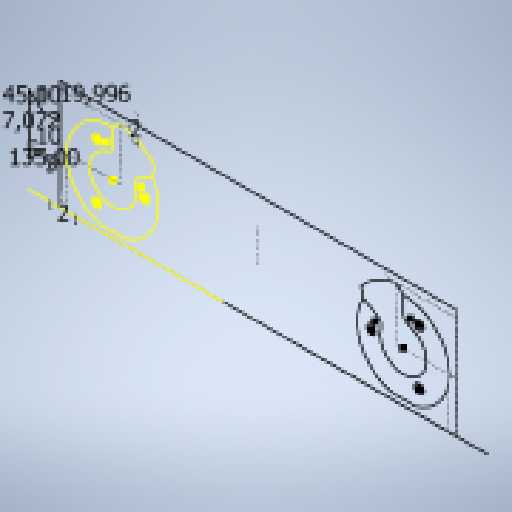
# Autodesk Inventor part: fast_motors
Saved by Autodesk Inventor 2025 (Build 290162000, 162)
## iProperties
Created: 2026-11-07
Part Number: fast_motors
Material: Типовые
Document SubType Name: Modeling
Designer: garin
Density: 1 g/cm^3
Appearance: По умолчанию
Author: garin
Autodesk Inventor part; units mm, degrees
ref_plane "YZ Plane" through (0, 0, 0) normal (1, 0, 0) x (0, 1, 0)
ref_plane "XZ Plane" through (0, 0, 0) normal (0, 1, 0) x (-1, 0, 0)
ref_plane "XY Plane" through (0, 0, 0) normal (0, 0, 1) x (1, 0, 0)
sketch "Эскиз1" plane through (0, 0, 0) normal (0, 0, 1) x (1, 0, 0)
  circle A0 centre (-45.542, 7.686) radius 1.3 projected
  circle A1 centre (-32.0424, -0.108) radius 1.3 projected
  circle A2 centre (-45.542, -7.902) radius 1.3 projected
  arc A3 (-41.0424, 12.892) -> (-44.6131, -12.608) centre (-41.0424, -0.108) ccw projected
  line L0 (-37.4717, -12.608) -> (-44.6131, -12.608) projected
  arc A4 (-37.4717, -12.608) -> (-29.7841, 6.392) centre (-41.0424, -0.108) ccw projected
  line L1 (-33.8879, 4.0227) -> (-29.7841, 6.392) projected
  arc A5 (-33.8879, 4.0227) -> (-34.8066, 1.7262) centre (-32.8879, 2.2906) ccw projected
  arc A6 (-42.5718, 6.2095) -> (-34.8066, 1.7262) centre (-41.0424, -0.108) ccw projected
  arc A7 (-42.5718, 6.2095) -> (-41.0424, 8.1534) centre (-43.0424, 8.1534) ccw projected
  line L2 (-41.0424, 12.892) -> (-41.0424, 8.1534) projected
  arc A8 (-29.1653, 9.0535) -> (-39.0468, 14.7587) centre (-41.0424, -0.108) ccw projected
  line L3 (-29.7841, 6.392) -> (-29.1653, 9.0535) projected
  line L4 (-39.0468, 14.7587) -> (-41.0424, 12.892) projected
  line L5 (-10, -14.25) -> (-65, -14.25) projected
  line L6 (-41.0424, -0.108) -> (-54.0424, -0.108) construction
  line L7 (-54.0424, -0.108) -> (-56.0424, -0.108) construction
  line L8 (-56.0424, -0.108) -> (-56.0424, -14.25) construction
  line L9 (-56.0424, -14.25) -> (-54.0424, -14.25) construction
  line L10 (-54.0424, -14.25) -> (-54.0424, -0.108) construction
  line L11 (-56.0424, -0.108) -> (-39.0468, -0.108) construction
  line L12 (-39.0468, -0.108) -> (-39.0468, 14.7587) construction
  line L13 (-39.0468, 14.7587) -> (-56.0424, 14.7587) construction
  line L14 (-56.0424, 14.7587) -> (-56.0424, -0.108) construction
  line L15 (-56.0424, 14.7587) -> (-36.0464, 14.7587) construction
  line L16 (-36.0464, 14.7587) -> (-36.0464, 16.7587) construction
  line L17 (-36.0464, 16.7587) -> (-56.0424, 16.7587) construction
  line L18 (-56.0424, 16.7587) -> (-56.0424, 14.7587) construction
  line L19 (0, 0) -> (0, 9.0535) construction
  circle A9 centre (45.542, 7.686) radius 1.3
  circle A10 centre (32.0424, -0.108) radius 1.3
  circle A11 centre (45.542, -7.902) radius 1.3
  arc A12 (44.6131, -12.608) -> (41.0424, 12.892) centre (41.0424, -0.108) ccw
  line L20 (37.4717, -12.608) -> (44.6131, -12.608)
  arc A13 (29.7841, 6.392) -> (37.4717, -12.608) centre (41.0424, -0.108) ccw
  line L21 (33.8879, 4.0227) -> (29.7841, 6.392)
  arc A14 (34.8066, 1.7262) -> (33.8879, 4.0227) centre (32.8879, 2.2906) ccw
  arc A15 (34.8066, 1.7262) -> (42.5718, 6.2095) centre (41.0424, -0.108) ccw
  arc A16 (41.0424, 8.1534) -> (42.5718, 6.2095) centre (43.0424, 8.1534) ccw
  line L22 (41.0424, 12.892) -> (41.0424, 8.1534)
  arc A17 (39.0468, 14.7587) -> (29.1653, 9.0535) centre (41.0424, -0.108) ccw
  line L23 (29.7841, 6.392) -> (29.1653, 9.0535)
  line L24 (39.0468, 14.7587) -> (41.0424, 12.892)
  line L25 (10, -14.25) -> (65, -14.25)
  line L26 (41.0424, -0.108) -> (54.0424, -0.108) construction
  line L27 (54.0424, -0.108) -> (56.0424, -0.108) construction
  line L28 (56.0424, -0.108) -> (56.0424, -14.25) construction
  line L29 (56.0424, -14.25) -> (54.0424, -14.25) construction
  line L30 (54.0424, -14.25) -> (54.0424, -0.108) construction
  line L31 (56.0424, -0.108) -> (39.0468, -0.108) construction
  line L32 (39.0468, -0.108) -> (39.0468, 14.7587) construction
  line L33 (39.0468, 14.7587) -> (56.0424, 14.7587) construction
  line L34 (56.0424, 14.7587) -> (56.0424, -0.108) construction
  line L35 (56.0424, 14.7587) -> (36.0464, 14.7587) construction
  line L36 (36.0464, 14.7587) -> (36.0464, 16.7587) construction
  line L37 (36.0464, 16.7587) -> (56.0424, 16.7587) construction
  line L38 (56.0424, 16.7587) -> (56.0424, 14.7587) construction
  line L39 (-56.0424, 16.7587) -> (56.0424, 16.7587)
  line L40 (56.0424, 16.7587) -> (56.0424, -14.25)
  line L41 (56.0424, -14.25) -> (-56.0424, -14.25)
  line L42 (-56.0424, -14.25) -> (-56.0424, 16.7587)
  line L43 (-56.0424, 16.7587) -> (-56.0424, 6.7587) construction
  line L44 (-56.0424, 6.7587) -> (-56.0424, -3.2413) construction
  line L45 (-56.0424, -14.25) -> (-56.0424, -4.25) construction
  line L46 (-56.0424, -4.25) -> (-56.0424, 5.75) construction
  line L47 (-56.0424, -4.25) -> (-61.6993, -9.9069)
  line L48 (-56.0424, -4.25) -> (-48.0424, -4.25) construction
  line L49 (-61.6993, -9.9069) -> (-61.6993, 11.4071)
  line L50 (-61.6993, 11.4071) -> (-56.0424, 5.75)
  line L51 (-61.6993, 0.7501) -> (-56.0424, 0.75) construction
  line L52 (56.0424, -4.25) -> (61.6993, -9.9069)
  line L53 (61.6993, -9.9069) -> (61.6993, 11.4071)
  line L54 (61.6993, 11.4071) -> (56.0424, 5.75)
  line L55 (-10, -11.75) -> (10, -11.75) projected
  line L56 (-10, -14.25) -> (-10, -11.75) projected
  line L57 (10, -11.75) -> (10, -14.25) projected
  line L58 (5.4, -6.25) -> (5.4, -10.25) projected
  line L59 (-5.4, -6.25) -> (5.4, -6.25) projected
  line L60 (-5.4, -10.25) -> (-5.4, -6.25) projected
  line L61 (5.4, -10.25) -> (-5.4, -10.25) projected
  dimension "d0" = 2
  dimension "d1" = 19.996
  dimension "d2" = 2
  dimension "d10" = 10
  dimension "d11" = 10
  dimension "d12" = 8
  dimension "d13" = 135
  dimension "d14" = 21.314
  constraints: 98 end point, 34 symmetric about line, 14 point on circle, 9 centre point, 8 parallel, 6 horizontal, 6 point on line, 4 perpendicular, 2 midpoint, 2 vertical, 1 equal length, 9 other
  measures "d0" distance of L9.end L8.end
  measures "d1" distance of L17.end L16.end
  measures "d2" distance of L16.end L15.end
  measures "d10" distance of L41.end L45.end
  measures "d11" distance of L45.end L46.end
  measures "d12" distance of L45.end L47.end
  measures "d13" angle of L47 L48
  measures "d14" distance of L47.end L49.end
extrude "Выдавливание1" add sketch "Эскиз1" along normal blind 5 contours L2 A7 A6 A5 L1 A4 L0 A3 | L5 L42 L39 L40 L25 L57 L55 L56 | L47 L49 L50 L42 | L40 L54 L53 L52 | L20 A13 L21 A14 A15 A16 L22 A12
chamfer "Фаска1" distance 3 angle 45 2 edges at (-56.0424, 16.7587, 2.5) (56.0424, 16.7587, 2.5)
